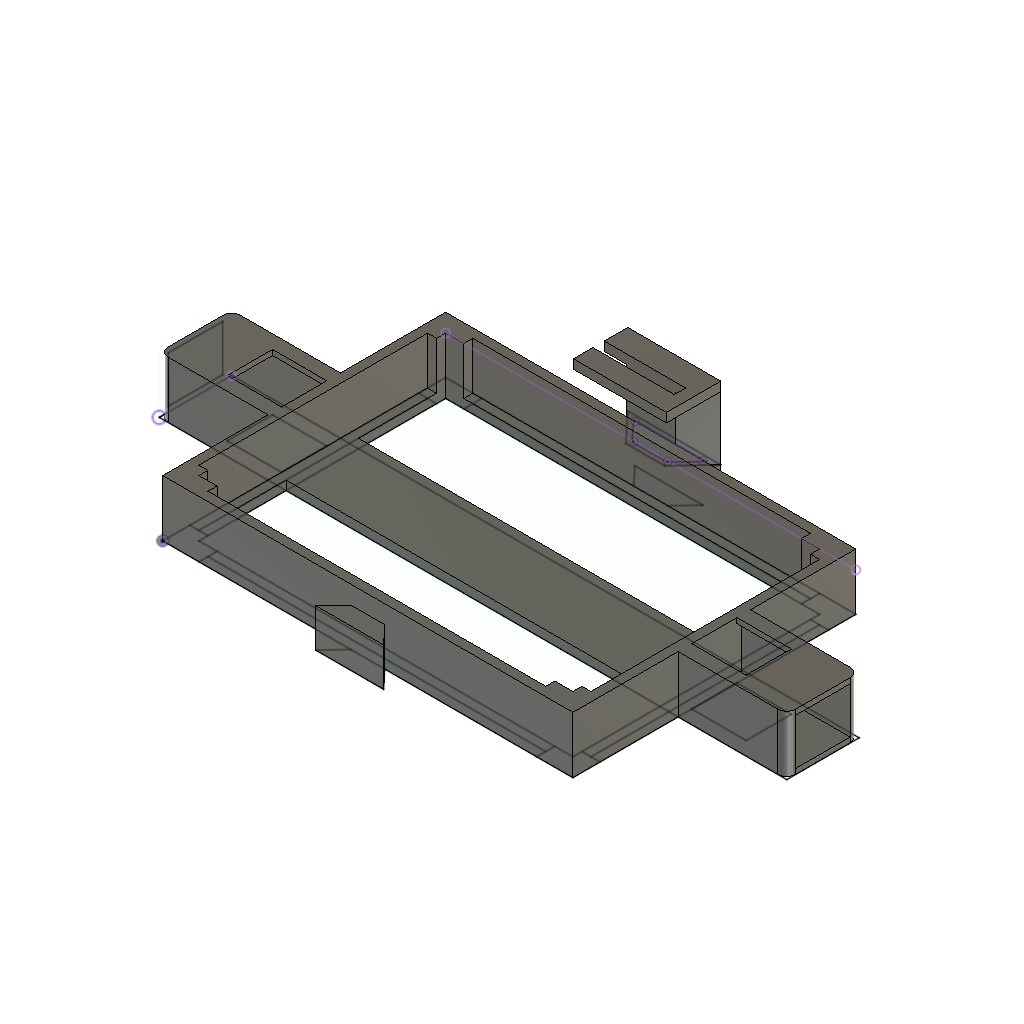
Self-balancing Robot (Autodesk Fusion 360 design; units mm, degrees)
part number: 2026-10-16-18-09-41-315
part number: 2026-10-16-18-09-51-928
part number: 2026-10-17-18-11-12-693
Autodesk Fusion 360 part; units mm, degrees
sketch "Sketch1" plane through (0, 0, 0) normal (0, 0, 1) x (1, 0, 0) in component "Base"
  line L0 (0, 0) -> (90.6, 0)
  line L1 (90.6, 0) -> (90.6, 62.5)
  line L2 (90.6, 62.5) -> (0, 62.5)
  line L3 (0, 62.5) -> (0, 0)
  line L4 (4, 4) -> (86.6, 4)
  line L5 (86.6, 4) -> (86.6, 58.5)
  line L6 (86.6, 58.5) -> (4, 58.5)
  line L7 (4, 58.5) -> (4, 4)
  line L8 (-24, 39.25) -> (114.6, 39.25)
  line L9 (114.6, 39.25) -> (114.6, 23.25)
  line L10 (114.6, 23.25) -> (-24, 23.25)
  line L11 (-24, 23.25) -> (-24, 39.25)
  line L12 (8, 62.5) -> (8, 58.5)
  line L13 (82.6, 62.5) -> (82.6, 58.5)
  line L14 (8, 4) -> (8, 0)
  line L15 (82.6, 4) -> (82.6, 0)
  line L16 (4, 56.5) -> (0, 56.5)
  line L17 (4, 6) -> (0, 6)
  line L18 (86.6, 56.5) -> (90.6, 56.5)
  line L19 (86.6, 6) -> (90.6, 6)
  line L20 (2, 56.5) -> (2, 6)
  line L21 (8, 60.5) -> (82.6, 60.5)
  line L22 (88.6, 56.5) -> (88.6, 6)
  line L23 (82.6, 2) -> (8, 2)
  line L24 (90.6, 26.25) -> (102.6, 26.25)
  line L25 (102.6, 26.25) -> (102.6, 36.25)
  line L26 (102.6, 36.25) -> (90.6, 36.25)
  line L27 (90.6, 36.25) -> (90.6, 26.25)
  line L28 (-12, 36.25) -> (-12, 26.25)
  line L29 (-12, 26.25) -> (0, 26.25)
  line L30 (0, 26.25) -> (0, 36.25)
  line L31 (0, 36.25) -> (-12, 36.25)
  line L32 (49.05, 62.5) -> (52.8, 66.5)
  line L33 (52.8, 66.5) -> (37.8, 66.5)
  line L34 (37.8, 66.5) -> (41.55, 62.5)
  line L35 (41.55, 0) -> (37.8, -4)
  line L36 (37.8, -4) -> (52.8, -4)
  line L37 (52.8, -4) -> (49.05, 0)
  dimension "d5" = 90.6
  dimension "d6" = 62.5
  dimension "d8" = 82.6
  dimension "d9" = 54.5
  dimension "d10" = 4
  dimension "d11" = 4
  dimension "d13" = 138.6
  dimension "d14" = 16
  dimension "d15" = 24
  dimension "d16" = 19.25
  dimension "d17" = 8
  dimension "d18" = 8
  dimension "d19" = 6
  dimension "d20" = 6
  dimension "d36" = 10
  dimension "d37" = 3
  dimension "d38" = 12
  dimension "d39" = 10
  dimension "d40" = 12
  dimension "d41" = 3
  dimension "d44" = 15
  dimension "d45" = 7.5
  dimension "d46" = 3.75
  dimension "d47" = 41.55
  dimension "d48" = 4
  dimension "d49" = 15
  dimension "d50" = 7.5
  dimension "d52" = 4
  dimension "d53" = 37.8
  dimension "d54" = 3.75
  constraint horizontal L0
  constraint vertical L1
  constraint horizontal L2
  constraint vertical L3
  constraint coincident L0.start L3.end
  constraint horizontal L4
  constraint vertical L5
  constraint horizontal L6
  constraint vertical L7
  constraint horizontal L8
  constraint vertical L9
  constraint horizontal L10
  constraint vertical L11
  constraint coincident L2 L12.start
  constraint coincident L6 L12.end
  constraint perpendicular L6 L12
  constraint coincident L2 L13.start
  constraint coincident L6 L13.end
  constraint perpendicular L6 L13
  constraint coincident L4 L14.start
  constraint coincident L0 L14.end
  constraint perpendicular L0 L14
  constraint coincident L4 L15.start
  constraint coincident L0 L15.end
  constraint perpendicular L0 L15
  constraint collinear L12 L14
  constraint collinear L13 L15
  constraint coincident L7 L16.start
  constraint coincident L3 L16.end
  constraint perpendicular L3 L16
  constraint coincident L7 L17.start
  constraint coincident L3 L17.end
  constraint perpendicular L3 L17
  constraint coincident L5 L18.start
  constraint coincident L1 L18.end
  constraint perpendicular L1 L18
  constraint coincident L5 L19.start
  constraint coincident L1 L19.end
  constraint perpendicular L1 L19
  constraint collinear L17 L19
  constraint collinear L16 L18
  constraint midpoint L16 L20.start
  constraint midpoint L17 L20.end
  constraint midpoint L12 L21.start
  constraint midpoint L13 L21.end
  constraint midpoint L18 L22.start
  constraint midpoint L19 L22.end
  constraint midpoint L15 L23.start
  constraint midpoint L14 L23.end
  constraint horizontal L24
  constraint vertical L25
  constraint horizontal L26
  constraint vertical L27
  constraint coincident L1 L24.start
  constraint horizontal L29
  constraint vertical L30
  constraint horizontal L31
  constraint vertical L28
  constraint collinear L3 L30
  constraint coincident L2 L32.start
  constraint parallel L2 L33
  constraint coincident L2 L34.end
  constraint coincident L0 L37.end
  constraint coincident L0 L35.start
  measures "d5" distance of L0.start L0.end
  measures "d6" distance of L0.start L2.end
  measures "d8" distance of L4.start L4.end
  measures "d9" distance of L4.start L6.end
  measures "d10" distance of L0 L4
  measures "d11" distance of L3 L7
  measures "d13" distance of L8.start L8.end
  measures "d14" distance of L8.start L10.end
  measures "d15" distance of L1 L9
  measures "d16" distance of L4 L10
  measures "d17" distance of L3 L12
  measures "d18" distance of L1 L13
  measures "d19" distance of L2 L16
  measures "d20" distance of L0 L17
  measures "d36" distance of L24 L26
  measures "d37" distance of L10 L24
  measures "d38" distance of L1 L25
  measures "d39" distance of L29 L31
  measures "d40" distance of L28 L30
  measures "d41" distance of L10 L29
  measures "d44" distance of L32.end L33.end
  measures "d45" distance of L32.start L34.end
  measures "d46" horizontal distance of L32.start L32.end
  measures "d47" distance of L1.end L32.start
  measures "d48" distance of L2 L33
  measures "d49" distance of L35.end L36.end
  measures "d50" distance of L37.end L35.start
  measures "d52" distance of L0 L36
  measures "d53" horizontal distance of L0.end L36.end
  measures "d54" horizontal distance of L35.end L35.start
extrude "Extrude1" add sketch "Sketch1" along normal blind 2 contours L0 L3 L4 L7 L14 L17 | L0 L14 L15 L23 | L3 L10 L17 L20 | L4 L14 L15 L23 | L3 L8 L10 L11 L28 L29 L31 | L3 L8 L10 L20 L30 | L7 L10 L17 L20 | L4 L5 L7 L10 | L0 L1 L4 L5 L15 L19 | L3 L28 L29 L30 L31 | L7 L8 L10 L20 | L5 L7 L8 L10 | L7 L8 L16 L20 | L3 L8 L16 L20 | L5 L6 L7 L8 | L5 L10 L19 L22 | L5 L8 L10 L22 | L2 L3 L6 L7 L12 L16 | L1 L10 L19 L22 | L5 L8 L18 L22 | L1 L8 L10 L22 L27 | L1 L8 L9 L10 L24 L25 L26 | L1 L2 L5 L6 L13 L18 | L1 L8 L18 L22 | L1 L24 L25 L26 L27 | L2 L12 L13 L21 | L6 L12 L13 L21 makes body 1 in component "Base"
sketch "Sketch2" plane through (0, 0, 2) normal (0, 0, 1) x (-1, 0, 0) in component "Base"
  line L0 (0, -23.25) -> (0, 0)
  line L1 (0, 0) -> (-90.6, 0)
  line L2 (-90.6, 0) -> (-90.6, -23.25)
  line L3 (-90.6, -23.25) -> (-114.6, -23.25)
  line L4 (-114.6, -23.25) -> (-114.6, -39.25)
  line L5 (-114.6, -39.25) -> (-90.6, -39.25)
  line L6 (-90.6, -39.25) -> (-90.6, -62.5)
  line L7 (-90.6, -62.5) -> (0, -62.5)
  line L8 (0, -62.5) -> (0, -39.25)
  line L9 (0, -39.25) -> (24, -39.25)
  line L10 (24, -39.25) -> (24, -23.25)
  line L11 (24, -23.25) -> (0, -23.25)
  line L12 (-86.6, -4) -> (-86.6, -58.5)
  line L13 (-88.6, -56.5) -> (-88.6, -6)
  line L14 (-90.6, 0) -> (-90.6, -62.5)
  line L15 (-86.6, -56.5) -> (-90.6, -56.5)
  line L16 (-82.6, -62.5) -> (-82.6, -58.5)
  line L17 (-8, -60.5) -> (-82.6, -60.5)
  line L18 (-86.6, -58.5) -> (-4, -58.5)
  line L19 (-90.6, -62.5) -> (0, -62.5)
  line L20 (-4, -4) -> (-86.6, -4)
  line L21 (-82.6, -2) -> (-8, -2)
  line L22 (-82.6, -4) -> (-82.6, 0)
  line L23 (-86.6, -6) -> (-90.6, -6)
  line L24 (-8, -4) -> (-8, 0)
  line L25 (-4, -6) -> (0, -6)
  line L26 (-2, -56.5) -> (-2, -6)
  line L27 (-4, -58.5) -> (-4, -4)
  line L28 (-4, -56.5) -> (0, -56.5)
  line L29 (-8, -62.5) -> (-8, -58.5)
extrude "Extrude2" add sketch "Sketch2" along normal blind 10.5 contours L0 L8 L9 L10 L11 L25 L26 L28 | L0 L1 L20 L24 L25 L27 | L1 L21 L22 L24 | L7 L8 L18 L19 L27 L28 L29 | L1 L2 L12 L14 L20 L22 L23 | L2 L6 L13 L14 L15 L23 | L7 L16 L17 L19 L29 | L3 L4 L5 L14 | L6 L7 L12 L14 L15 L16 L18 L19 bodies 1 in component "Base"
sketch "Sketch3" plane through (-24, 0, 0) normal (-1, 0, 0) x (0, -1, 0) in component "Base"
  line L0 (-39.25, 0) -> (-23.25, 0)
  line L1 (-23.25, 0) -> (-23.25, 12.5)
  line L2 (-23.25, 12.5) -> (-39.25, 12.5)
  line L3 (-39.25, 12.5) -> (-39.25, 0)
  line L4 (-37.25, 1.15) -> (-25.25, 1.15)
  line L5 (-25.25, 1.15) -> (-25.25, 11.35)
  line L6 (-25.25, 11.35) -> (-37.25, 11.35)
  line L7 (-37.25, 11.35) -> (-37.25, 1.15)
  line L8 (-23.25, 0) -> (-39.25, 0)
  dimension "d26" = 10.2
  dimension "d27" = 12
  dimension "d28" = 16
  dimension "d29" = 2
  dimension "d30" = 12.5
  dimension "d31" = 1.15
  measures "d26" distance of L4 L6
  measures "d27" distance of L5 L7
  measures "d28" distance of L0.end L0.start
  measures "d29" distance of L3 L7
  measures "d30" distance of L0.end L1.end
  measures "d31" distance of L2 L6
extrude "Extrude3" cut sketch "Sketch3" against normal blind 24 contours L4 L5 L6 L7 bodies 1 in component "Base"
sketch "Sketch5" plane through (114.6, 0, 0) normal (1, 0, 0) x (0, 1, 0) in component "Base"
  line L0 (23.25, 0) -> (39.25, 0)
  line L1 (39.25, 0) -> (39.25, 12.5)
  line L2 (39.25, 12.5) -> (23.25, 12.5)
  line L3 (23.25, 12.5) -> (23.25, 0)
  line L4 (25.25, 1.15) -> (25.25, 11.35)
  line L5 (25.25, 11.35) -> (37.25, 11.35)
  line L6 (37.25, 11.35) -> (37.25, 1.15)
  line L7 (37.25, 1.15) -> (25.25, 1.15)
extrude "Extrude4" cut sketch "Sketch5" against normal blind 24 contours L4 L5 L6 L7 bodies 1 in component "Base"
extrude "Extrude5" cut sketch "Sketch1" along normal blind 12.5 contours L4 L5 L7 L10 | L3 L28 L29 L30 L31 | L5 L6 L7 L8 | L1 L24 L25 L26 L27 bodies 1 in component "Base"
extrude "Extrude6" add sketch "Sketch1" along normal blind 8.5 contours L0 L35 L36 L37 | L2 L32 L33 L34 bodies 1 in component "Base"
sketch "Sketch1 (2)" plane through (0, 0, 8.5) normal (0, 0, 1) x (-1, 0, 0) in component "MPUHolder"
  line L0 (-49.05, -62.5) -> (-52.8, -66.5)
  line L1 (-52.8, -66.5) -> (-37.8, -66.5)
  line L2 (-37.8, -66.5) -> (-41.55, -62.5)
  line L3 (-41.55, -62.5) -> (-49.05, -62.5)
  line L4 (-53.2616, -66.7) -> (-37.3384, -66.7)
  line L5 (-37.3384, -66.7) -> (-41.4634, -62.3)
  line L6 (-41.4634, -62.3) -> (-49.1366, -62.3)
  line L7 (-49.1366, -62.3) -> (-53.2616, -66.7)
  line L8 (-55.5699, -67.7) -> (-35.0301, -67.7)
  line L9 (-35.0301, -67.7) -> (-41.0301, -61.3)
  line L10 (-41.0301, -61.3) -> (-49.5699, -61.3)
  line L11 (-49.5699, -61.3) -> (-55.5699, -67.7)
  line L12 (-90.6, -62.5) -> (0, -62.5)
  dimension "d57" = 0.2
  dimension "d58" = 1
extrude "Extrude1'" add sketch "Sketch1 (2)" against normal blind 8.5 separate body contours L4 L5 L7 L8 L9 L11 L12 makes body 2 in component "MPUHolder"
extrude "Extrude2'" add sketch "Sketch1 (2)" along normal blind 16 contours L0 L1 L2 L3 L12 | L0 L1 L2 L4 L5 L7 L12 | L4 L5 L7 L8 L9 L11 L12 bodies 2 in component "MPUHolder"
sketch "Sketch2 (2)" plane through (0, 0, 24.5) normal (0, 0, 1) x (-1, 0, 0) in component "MPUHolder"
  line L0 (-39.9051, -62.5) -> (-50.6949, -62.5)
  line L1 (-50.6949, -62.5) -> (-55.5699, -67.7)
  line L2 (-55.5699, -67.7) -> (-35.0301, -67.7)
  line L3 (-35.0301, -67.7) -> (-39.9051, -62.5)
  line L4 (-55.5699, -67.7) -> (-55.5699, -55.7)
  line L5 (-35.0301, -67.7) -> (-35.0301, -55.7)
  line L6 (-35.0301, -55.7) -> (-55.5699, -55.7)
  line L7 (-35.0301, -60) -> (-53.0301, -60)
  line L8 (-53.0301, -60) -> (-53.0301, -62.5)
  line L9 (-53.0301, -62.5) -> (-35.0301, -62.5)
  dimension "d65" = 12
  dimension "d66" = 18
  dimension "d67" = 2.5
  constraint coincident L1.end L2.start
  constraint perpendicular L2 L4
  constraint coincident L2.end L3.start
  constraint perpendicular L2 L5
  constraint perpendicular L4 L6
  constraint coincident L5 L7.start
  constraint perpendicular L4 L7
  constraint perpendicular L6 L8
  constraint coincident L5 L9.end
  constraint perpendicular L5 L9
  constraint collinear L0 L9
  measures "d65" distance of L1.end L4.end
  measures "d66" distance of L7.start L7.end
  measures "d67" distance of L7 L9
extrude "Extrude3'" add sketch "Sketch2 (2)" against normal blind 2 contours L3 L5 L9 | L1 L4 L5 L6 L7 L8 L9 bodies 2 in component "MPUHolder"
fillet "Fillet1" radius 2 2 edges at (114.6, 23.25, 6.25) (114.6, 39.25, 6.25) on bodies 1 in component "Base"
fillet "Fillet2" radius 2 2 edges at (-24, 23.25, 6.25) (-24, 39.25, 6.25) on bodies 1 in component "Base"
component "Base" placed x (1, 0, 0) y (0, 1, 0) z (0, 0, 1) at (0, 0, 0)
component "MPUHolder" placed x (1, 0, 0) y (0, 1, 0) z (0, 0, 1) at (0, 0, 0)
equation "Length = 82.6 mm"
equation "Width = 54.5 mm"
equation "MotorHoleHight = 10.7 mm"
equation "MotorHoleWidth = 12 mm"
equation "d5 = Length + Thickness * 2"
equation "d6 = Width + Thickness * 2"
equation "Thickness = 4 mm"
equation "d8 = Length"
equation "d9 = Width"
equation "d10 = Thickness"
equation "d11 = Thickness"
equation "MotorHoleLength = 24 mm"
equation "d13 = MotorHoleLength * 2 + Length + Thickness * 2"
equation "d14 = MotorHoleWidth + Thickness"
equation "d15 = MotorHoleLength"
equation "d16 = Width / 2 - d14 / 2"
equation "d17 = Thickness * 2"
equation "d18 = d17"
equation "d19 = Thickness * 1.5"
equation "d20 = d19"
equation "d21 = Thickness / 2"
equation "d23 = 12.5 mm - Thickness / 2"
equation "d29 = d28 / 2 - d27 / 2"
equation "d31 = d30 / 2 - d26 / 2"
equation "d32 = -26.00 mm + Thickness / 2"
equation "d34 = -26.00 mm + Thickness / 2"
equation "d37 = d14 / 2 - d36 / 2"
equation "d38 = d40"
equation "d40 = Thickness * 3"
equation "d41 = d37"
equation "d45 = d44 / 2"
equation "d46 = d44 / 4"
equation "d47 = d5 / 2 - d45 / 2"
equation "d48 = Thickness"
equation "d50 = d44 / 2"
equation "d52 = Thickness"
equation "d53 = d5 / 2 - d49 / 2"
equation "d54 = d49 / 4"
equation "d55 = 12.50 mm - Thickness"
equation "d57 = Thickness / 20"
equation "d58 = Thickness / 4"
equation "d63 = Thickness * 4"
equation "d65 = Thickness * 3"
equation "d68 = -Thickness / 2"
